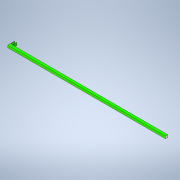
# Autodesk Inventor part: suport_balustrada_orizontala
Saved by Autodesk Inventor 2022.6 (Build 266554000, 554)
## iProperties
Created: 2026-11-02
Part Number: suport_balustrada_orizontala
Material: Generic
Document SubType Name: Modeling
Designer: Dragos Macovei
Density: 1 g/cm^3
Appearance: Default
Author: Dragos Macovei
Autodesk Inventor part; units mm, degrees
ref_plane "YZ Plane" through (0, 0, 0) normal (1, 0, 0) x (0, 1, 0)
ref_plane "XZ Plane" through (0, 0, 0) normal (0, 1, 0) x (-1, 0, 0)
ref_plane "XY Plane" through (0, 0, 0) normal (0, 0, 1) x (1, 0, 0)
sketch "Sketch1" plane through (0, 0, 0) normal (0, 1, 0) x (-1, 0, 0)
  line L0 (21, 0) -> (21, 40)
  line L1 (21, 40) -> (3, 40)
  line L2 (3, 40) -> (3, 0)
  line L3 (3, 0) -> (0, 0)
  line L4 (0, 0) -> (0, 43)
  line L5 (0, 43) -> (24, 43)
  line L6 (24, 43) -> (24, 0)
  line L7 (24, 0) -> (21, 0)
  line L8 (24, 0) -> (21, 0)
  line L9 (21, 0) -> (21, 68)
  line L10 (21, 68) -> (24, 68)
  line L11 (24, 68) -> (24, 0)
  point P0 (12, 40)
  point P1 (22.5, 68)
  point P2 (21, 43)
  point P3 (24, 43)
  point P4 (22.5, 0)
  dimension "d0" = 3
  dimension "d1" = 3
  dimension "d2" = 3
  dimension "d18" = 25
  dimension "d20" = 40
  constraints: 24 end point, 8 perpendicular, 3 midpoint, 2 parallel, 1 horizontal, 1 point on line, 1 vertical
  measures "d0" distance between parallel lines of L0 L6
  measures "d1" distance from line of L5 point (12, 40)
  measures "d2" distance between parallel lines of L4 L2
  measures "d18" distance from line of point (22.5, 68) L5
  measures "d20" distance from line of point (22.5, 0) L1
extrude "Extrusion1" add sketch "Sketch1" along normal blind 24
sketch "Sketch2" plane through (-24, 0, 43) normal (0, 0, 1) x (1, 0, 0)
  line L0 (3, 0) -> (24, 0) projected
  line L1 (24, 0) -> (24, 24) projected
  line L2 (3, 24) -> (24, 24) projected
  line L3 (3, 0) -> (3, 24) projected
  line L4 (3, 0) -> (24, 0) projected
  line L5 (24, 0) -> (24, 24) projected
  line L6 (3, 24) -> (24, 24) projected
  line L7 (3, 0) -> (3, 24) projected
  circle A0 centre (13.5, 12) radius 10.5
  line L8 (24, 0) -> (24, 24) projected
  point P0 (3, 12)
  point P1 (24, 12)
  constraints: 1 centre point, 1 tangent
extrude "Extrusion2" add sketch "Sketch2" along normal up to surface (25 mm away)
sketch "Sketch5" plane through (0, 0, 43) normal (1, 0, 0) x (0, 0, -1)
  line L0 (0, 24) -> (0, 12) projected
  line L1 (0, 0) -> (0, 4.0627) projected
  line L2 (0, 19.9373) -> (0, 24) projected
  line L3 (0, 12) -> (0, 0) projected
  line L4 (0, 4.0627) -> (-25, 4.0627) projected
  line L5 (-25, 19.9373) -> (0, 19.9373) projected
  line L6 (-25, 19.9373) -> (-25, 4.0627) projected
  line L7 (-25, 0) -> (-25, 24) projected
  line L8 (-25, 0) -> (0, 0) projected
  line L9 (-25, 24) -> (-1, 24)
  line L10 (-1, 24) -> (-1, 0)
  line L11 (-1, 0) -> (-25, 0)
  line L12 (-25, 0) -> (-25, 24)
  point P0 (43, 0)
  point P1 (0, 4.0627)
  point P2 (0, 19.9373)
  point P3 (-11.1471, 12)
  dimension "d21" = 24
  dimension "d22" = 1
  constraints: 8 end point, 2 parallel, 1 horizontal, 1 perpendicular, 1 point on line
  measures "d21" distance of L10.end L11.end
  measures "d22" distance between parallel lines of L0 L10
extrude "Extrusion4" add sketch "Sketch5" along normal blind 1576 and the other way blind 24 contours L10 L4 L6 L5 | L5 L7 L9 L10 | L10 L8 L7 L4
body "Solid1"
